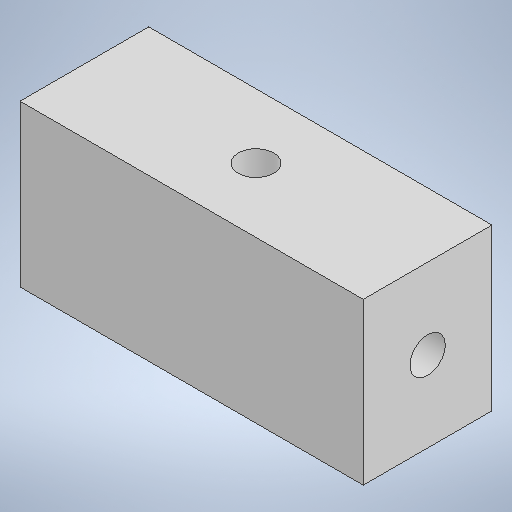
# Autodesk Inventor part: AP12.0_rotery-joint
Saved by Autodesk Inventor 2025.3 (Build 293356030, 356C)
## iProperties
Created: 2026-01-04
Part Number: AP12.0_rotery-joint
Material: 一般
Document SubType Name: Modeling
Designer: ibuki_ono
Density: 1 g/cm^3
Appearance: 既定
Author: ibuki_ono
Autodesk Inventor part; units mm, degrees
ref_plane "YZ Plane" through (0, 0, 0) normal (1, 0, 0) x (0, 1, 0)
ref_plane "XZ Plane" through (0, 0, 0) normal (0, 1, 0) x (-1, 0, 0)
ref_plane "XY Plane" through (0, 0, 0) normal (0, 0, 1) x (1, 0, 0)
sketch "スケッチ1" plane through (0, 0, 0) normal (0, 0, 1) x (1, 0, 0)
  line L0 (-16, -7.5) -> (16, -7.5)
  line L1 (16, -7.5) -> (16, 7.5)
  line L2 (16, 7.5) -> (-16, 7.5)
  line L3 (-16, 7.5) -> (-16, -7.5)
  line L4 (-16, -7.5) -> (16, 7.5) construction
  line L5 (16, -7.5) -> (-16, 7.5) construction
  point P0 (0, 0)
  dimension "d0" = 32
  dimension "d1" = 15
  constraints: 12 end point, 2 midpoint, 2 parallel, 1 horizontal, 1 perpendicular
  measures "d0" distance of L2.end L1.end
  measures "d1" distance of L1.end L0.end
extrude "押し出し1" add sketch "スケッチ1" along normal mid plane 12
sketch "スケッチ2" plane through (-16, -7.5, 6) normal (0, -1, 0) x (1, 0, 0)
  point P0 (16, -6)
  point P1 (16, -6)
  constraints: 1 coincident
hole "穴1" at (0, -7.5, 0) direction (0, 1, 0) diameter 3.3 end through all
sketch "スケッチ3" plane through (-16, -7.5, 6) normal (-1, 0, 0) x (0, 0, 1)
  point P0 (-6, 7.5)
  point P1 (-6, 7.5)
  constraints: 1 coincident
hole "穴2" at (-16, 0, 0) direction (1, 0, 0) diameter 3.3 end through all
